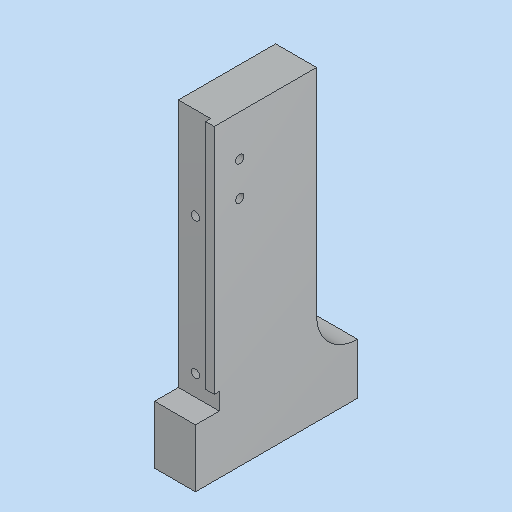
# Autodesk Inventor part: MM0948AN100_G01_112
Saved by Autodesk Inventor 2023.3 (Build 273359000, 359)
## iProperties
Part Number: MM0948AN100_G01_112
Material: 3.3547 AlMg4,5Mn0,7 - AW 5083
Description: =<RBPARTNOTITLE2>
Document SubType Name: Modeling
Designer: ric7an
Mass: 92.5617 g
Surface Area: 100.924 cm^2
Volume: 34.2821 cm^3
Density: 2.7 g/cm^3
Appearance: Aluminium AnP
Created: 2023-03-23
RBDOCUMENTTYPE: DRF
RBDOCUMENTVERSION: 00
RBDRAWINGMAINSCALE: 1:1
RBDRAWINGMISSINGSPEC: --
RBDRAWINGVOLUME: --
RBGBEDGESIN1: +0,5
RBGBEDGESIN2: +0,2
RBGBEDGESOUT1: -0,3
RBGBEDGESOUT2: -0,1
RBMATERIAL: =<Material>
RBMATMEETS: --
RBMATNO: =<Part Number>
RBPARTMADEOF: 12 x 90 x 47,5 (FM)
RBPARTNO: SIEHE MNR
RBPARTNOTITLE1: manufactured part
RBPARTNOTITLE2: Anfertigungsteil
RBPARTSAFETYINDICATOR: --
RBSURFACE: hard-coated  475 HV ± 25, 40 μm coating thickness
RBSURFACE2: hartcoatiert 475 HV ± 25, 40 μm Schicht
RBZEDGESNORM: ISO13715:2002-06
RBZGENDIMCLASS: m
RBZGENDIMNORM: ISO 2768-1:1989-11
RBZGENGEOCLASS: H
RBZGENGEONORM: ISO 2768-2:1989-11
RBZSURFACENORM: ISO13D2:2002-02
RBZTOLERANCENORM: ISO 14405-1:2010-12
AnP_Material: =<Material>
AnP_TemplVers: 20190222
AnP_Kategorie: 1
MaxAbmaße: 12 x 90 x 47,5 (FM)
AnP_Kommentar_aktuell: =<Comments>
AnP_Material_aktuell: =<Material>
Author: FH/Wi
Keywords: =<RBPARTMADEOF>
Comments: =<RBSURFACE2>
Revision Number: 01
Autodesk Inventor part; units mm, degrees
ref_plane "YZ Plane" through (0, 0, 0) normal (1, 0, 0) x (0, 1, 0)
ref_plane "XZ Plane" through (0, 0, 0) normal (0, 1, 0) x (-1, 0, 0)
ref_plane "XY Plane" through (0, 0, 0) normal (0, 0, 1) x (1, 0, 0)
sketch "Skizze1" plane through (0, 0, 0) normal (0, 0, 1) x (1, 0, 0)
  line L0 (0, 0) -> (30, 0)
  line L1 (30, 0) -> (30, 90)
  line L2 (30, 90) -> (0, 90)
  line L3 (0, 90) -> (0, 0)
  line L4 (30, 15) -> (73.75, 15)
  line L5 (73.75, 15) -> (73.75, 0)
  line L6 (73.75, 0) -> (30, 0)
  line L7 (30, 0) -> (30, 15)
  dimension "d0" = 30
  dimension "d1" = 73.75
  dimension "d2" = 15
  dimension "d3" = 90
  constraints: 16 end point, 4 parallel, 2 horizontal, 2 perpendicular, 2 point on line
  measures "d0" distance of L1.end L2.end
  measures "d1" distance between parallel lines of L5 L3
  measures "d2" distance of L4.end L5.end
  measures "d3" distance of L2.end L0.start
extrude "Extrusion1" add sketch "Skizze1" along normal mid plane 12
fillet "Rundung1" radius 12 1 edges at (30, 15, 0)
sketch "Skizze2" plane through (0, 0, 6) normal (-1, 0, 0) x (0, 0, 1)
  line L0 (0, 0) -> (-12, 0) projected
  line L1 (0, 90) -> (0, 0) projected
  line L2 (-12, 90) -> (0, 90) projected
  line L3 (-12, 0) -> (-12, 90) projected
  line L4 (-12, 90) -> (-2.5, 90)
  line L5 (-2.5, 90) -> (-2.5, 0)
  line L6 (-2.5, 0) -> (-12, 0)
  line L7 (-12, 0) -> (-12, 90)
  point P0 (-6, 0)
  dimension "d7" = 2.5
  constraints: 8 end point, 2 parallel, 1 horizontal, 1 perpendicular, 1 point on line
  measures "d7" distance between parallel lines of L1 L5
extrude "Extrusion2" cut sketch "Skizze2" against normal blind 1.5 contours L0 L3 L2 L5
sketch "Skizze3" plane through (1.5, 0, 6) normal (-1, 0, 0) x (0, 0, 1)
  line L0 (-12, 0) -> (-12, 90) projected
  line L1 (-2.5, 0) -> (-12, 0) projected
  line L2 (-12, 90) -> (-2.5, 90) projected
  line L3 (-2.5, 90) -> (-2.5, 0) projected
  point P0 (-6, 0)
  point P1 (-7, 63)
  point P2 (-7, 23)
  dimension "d11" = 40
  dimension "d47" = 27
  dimension "d66" = 4.5
  constraints: 1 vertical alignment
  measures "d11" distance of point (-7, 23) point (-7, 63)
  measures "d47" distance from line of L2 point (-7, 63)
  measures "d66" distance from line of L3 point (-7, 63)
hole "Bohrung1" at (1.5, 63, -1) at (1.5, 23, -1) direction (1, 0, 0) diameter 2.459 depth 8.8 tip angle 118 thread size "M3x0.5" designation "M3" class "6H" standard "ISO Metric profile"
sketch "Skizze6" plane through (1.5, 0, 6) normal (-1, 0, 0) x (0, 0, 1)
  circle A0 centre (-7, 63) radius 1.2295 projected
  circle A1 centre (-7, 23) radius 1.2295 projected
  line L0 (-2.5, 90) -> (-2.5, 0) projected
  line L1 (-12, 90) -> (-2.5, 90) projected
  line L2 (-12, 0) -> (-12, 90) projected
  line L3 (-2.5, 0) -> (-12, 0) projected
  line L4 (-12, 0) -> (0, 0)
  line L5 (0, 0) -> (0, 17)
  line L6 (0, 17) -> (-12, 17)
  line L7 (-12, 17) -> (-12, 0)
  line L8 (0, 90) -> (0, 0) projected
  point P0 (-6, 0)
  dimension "d50" = 17
  constraints: 8 end point, 2 parallel, 1 collinear, 1 horizontal, 1 perpendicular
  measures "d50" distance between parallel lines of L3 L6
extrude "Extrusion3" add sketch "Skizze6" along normal blind 7 contours L6 L5 L4 L0 | L0 L3 L2 L6
sketch "Skizze7" plane through (0, 90, 3.5) normal (-1, 0, 0) x (0, 0, 1)
  line L0 (0, -73) -> (2.5, -73) projected
  line L1 (2.5, 0) -> (2.5, -73) projected
  line L2 (0, 0) -> (2.5, 0) projected
  line L3 (0, 0) -> (0, -73) projected
  line L4 (0, -73) -> (2.5, -73)
  line L5 (2.5, -73) -> (2.5, -68)
  line L6 (2.5, -68) -> (0, -68)
  line L7 (0, -68) -> (0, -73)
  point P0 (-3.5, -90)
  dimension "d53" = 5
  constraints: 8 end point, 2 parallel, 1 horizontal, 1 perpendicular, 1 point on line
  measures "d53" distance between parallel lines of L0 L6
extrude "Extrusion4" cut sketch "Skizze7" against normal up to surface (1.5 mm away) contours L3 L6 L1 L0
sketch "Skizze8" plane through (0, 0, -6) normal (0, 0, -1) x (-1, 0, 0)
  line L0 (-1.5, 17) -> (-1.5, 90) projected
  line L1 (-1.5, 90) -> (-30, 90) projected
  point P0 (0, 0)
  point P1 (-7.5, 78)
  point P2 (-7.5, 68)
  dimension "d56" = 6
  dimension "d57" = 10
  dimension "d65" = 12
  constraints: 1 vertical alignment
  measures "d56" distance from line of L0 point (-7.5, 78)
  measures "d57" distance of point (-7.5, 68) point (-7.5, 78)
  measures "d65" distance from line of L1 point (-7.5, 78)
hole "Bohrung5" at (7.5, 78, -6) at (7.5, 68, -6) direction (0, 0, 1) diameter 2.459 end through all thread size "M3x0.5" designation "M3" class "6H" standard "ISO Metric profile"
sketch "Skizze4" plane through (0, 0, 6) normal (0, -1, 0) x (1, 0, 0)
  line L0 (0, 2.4) -> (0, -14.4) projected
  line L1 (-21.35, -6) -> (89.6, -6) projected
  line L2 (1.5, -2.5) -> (1.5, -12) projected
  line L3 (73.75, 0) -> (73.75, -12) projected
  line L4 (-5.5, -12) -> (-5.5, 0) projected
  point P0 (0, -6)
  point P1 (-0.5, -6)
  point P2 (6.5, -6)
  point P3 (29.5, -6)
  point P4 (36.5, -6)
  dimension "d67" = 23
  dimension "d69" = 7
  dimension "d70" = 7
  dimension "d72" = 5
  constraints: 3 horizontal alignment, 1 point on line
  measures "d67" distance of point (29.5, -6) point (6.5, -6)
  measures "d69" distance of point (6.5, -6) point (-0.5, -6)
  measures "d70" distance of point (36.5, -6) point (29.5, -6)
  measures "d72" distance from line of point (-0.5, -6) L4
hole "Bohrung3" at (-0.5, 0, 0) at (36.5, 0, 0) direction (0, 1, 0) diameter 4 depth 12 tip angle 118
hole "Bohrung2" at (6.5, 0, 0) at (29.5, 0, 0) direction (0, 1, 0) diameter 3.242 depth 11.8 tip angle 118 thread size "M4x0.7" designation "M4" class "6H" standard "ISO Metric profile"
sketch "Skizze9" plane through (0, 0, 6) normal (0, 0, 1) x (1, 0, 0)
  line L0 (42, 15) -> (73.75, 15)
  line L1 (73.75, 15) -> (73.75, 0)
  line L2 (73.75, 0) -> (42, 0)
  line L3 (42, 0) -> (42, 15)
  line L4 (73.75, 0) -> (73.75, 15) projected
  line L5 (73.75, 15) -> (73.75, 0) projected
  line L6 (8.121, 0) -> (4.879, 0) projected
  line L7 (31.121, 0) -> (27.879, 0) projected
  line L8 (1.5, 0) -> (-2.5, 0) projected
  line L9 (38.5, 0) -> (34.5, 0) projected
  line L10 (73.75, 0) -> (-5.5, 0) projected
  line L11 (-5.5, 0) -> (73.75, 0) projected
  line L12 (73.75, 15) -> (42, 15) projected
  line L13 (42, 15) -> (73.75, 15) projected
  arc A0 (30, 27) -> (42, 15) centre (42, 27) ccw projected
  arc A1 (30, 27) -> (42, 15) centre (42, 27) ccw projected
  line L14 (73.75, 15) -> (42, 15) projected
  line L15 (73.75, 0) -> (73.75, 15) projected
  line L16 (-5.5, 0) -> (73.75, 0) projected
  point P0 (0, 0)
  constraints: 8 end point, 2 collinear, 2 horizontal, 2 parallel, 1 perpendicular, 1 point on line, 1 other
extrude "Extrusion5" cut sketch "Skizze9" against normal through all
